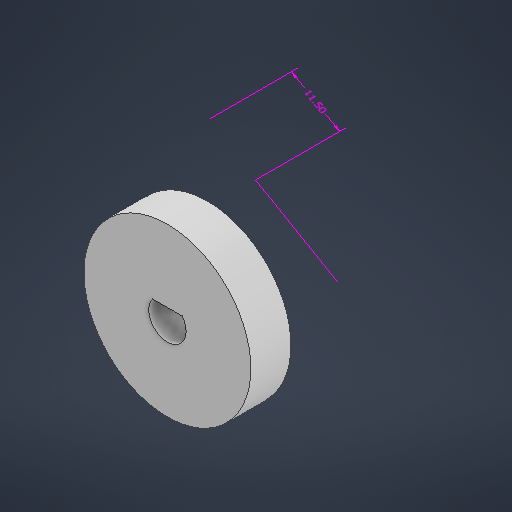
# Autodesk Inventor part: MoonBuggyWheelAdaptor_circle
Saved by Autodesk Inventor 2026.3 (Build 303398000, 398)
## iProperties
Created: 2026-07-29
Part Number: MoonBuggyWheelAdaptor_circle
Material: Generic
Document SubType Name: Modeling
Designer: dmr556
Density: 1 g/cm^3
Appearance: Default
Author: dmr556
Autodesk Inventor part; units mm, degrees
ref_plane "YZ Plane" through (0, 0, 0) normal (1, 0, 0) x (0, 1, 0)
ref_plane "XZ Plane" through (0, 0, 0) normal (0, 1, 0) x (-1, 0, 0)
ref_plane "XY Plane" through (0, 0, 0) normal (0, 0, 1) x (1, 0, 0)
sketch "Sketch1" plane through (0, 0, 0) normal (0, 0, 1) x (1, 0, 0)
  circle A0 centre (0, 0) radius 1.4
  line L0 (-5.1261, 0.85) -> (5.6295, 0.85)
  circle A1 centre (0, 11.5) radius 1.5
  line L1 (0, 11.5) -> (3.96, 11.5) construction
  circle A2 centre (-9.9593, 5.75) radius 1.5
  circle A3 centre (-9.9593, -5.75) radius 1.5
  circle A4 centre (0, -11.5) radius 1.5
  circle A5 centre (9.9593, -5.75) radius 1.5
  circle A6 centre (9.9593, 5.75) radius 1.5
  line L2 (0, 11.5) -> (0, -11.5)
  circle A7 centre (0, 0) radius 17.5
  point P0 (-48.6035, 11.3043)
  point P1 (-50.8284, 11.3043)
  point P2 (-45.8224, 23.6768)
  point P3 (-1.1124, 0.85)
  point P4 (1.1124, 0.85)
  dimension "d0" = 2.8
  dimension "d1" = 0.85
  dimension "d3" = 3
  dimension "d7" = 360
  dimension "d9" = 20
  dimension "d10" = 23
  dimension "d11" = 35
  dimension "d15" = 26
  constraints: 8 centre point, 6 end point, 3 coincident, 2 horizontal, 1 vertical, 13 other
  measures "d0" diameter of A0
  measures "d1" distance from line of L0 point (0, 0)
  measures "d3" diameter of A1
  measures "d10" distance of L2.end A1.centre
  measures "d11" diameter of A7
extrude "Extrusion1" add sketch "Sketch1" along normal blind 3 contours L0 L2 A0 | L2 L0 A0 | A7 picked at (0.6674, 0.927) picked at (-0.6674, 0.927)
sketch "Sketch2" plane through (0, 0, 3) normal (0, 0, 1) x (1, 0, 0)
  arc A0 (-1.1124, 0.85) -> (1.1124, 0.85) centre (0, 0) ccw projected
  circle A1 centre (0, 0) radius 6.25
  line L0 (-28.1697, 19.9039) -> (33.5158, 19.9039)
  line L1 (33.5158, 19.9039) -> (33.5158, -19.4104)
  line L2 (33.5158, -19.4104) -> (-28.1697, -19.4104)
  line L3 (-28.1697, -19.4104) -> (-28.1697, 19.9039)
  dimension "d16" = 12.5
  constraints: 8 end point, 2 parallel, 1 centre point, 1 coincident, 1 horizontal, 1 perpendicular
  measures "d16" diameter of A1
extrude "Extrusion2" cut sketch "Sketch2" against normal blind 10
body "Solid1"
